Autodesk Inventor part; units mm, degrees
(part 2 of 2)
  line L877 (-195.7056, 97.218) -> (-199.6927, 97.218)
  line L878 (-201.2028, 79.0886) -> (-201.786, 79.1114)
  line L879 (-201.786, 79.1114) -> (-202.2096, 79.1804)
  line L880 (-202.2096, 79.1804) -> (-202.5152, 79.3162)
  line L881 (-202.5152, 79.3162) -> (-202.7369, 79.5481)
  line L882 (-202.7369, 79.5481) -> (-202.8877, 79.8825)
  line L883 (-202.8877, 79.8825) -> (-202.9805, 80.3189)
  line L884 (-202.9805, 80.3189) -> (-203.0286, 80.9114)
  line L885 (-203.0286, 80.9114) -> (-203.0444, 81.7214)
  line L886 (-203.0444, 81.7214) -> (-203.0056, 83.461)
  line L887 (-203.0056, 83.461) -> (-202.8887, 85.3009)
  line L888 (-202.8887, 85.3009) -> (-202.8067, 86.2924)
  line L889 (-202.8067, 86.2924) -> (-202.7609, 86.8629)
  line L890 (-202.7609, 86.8629) -> (-213.2957, 86.8629)
  line L891 (-213.2957, 86.8629) -> (-213.2957, 82.5403)
  line L892 (-213.2957, 82.5403) -> (-206.8037, 82.5403)
  line L893 (-206.8037, 82.5403) -> (-206.8797, 81.6973)
  line L894 (-206.8797, 81.6973) -> (-206.9367, 80.188)
  line L895 (-206.9367, 80.188) -> (-206.9556, 79.1924)
  line L896 (-206.9556, 79.1924) -> (-206.9328, 78.4594)
  line L897 (-206.9328, 78.4594) -> (-206.7505, 77.1615)
  line L898 (-206.7505, 77.1615) -> (-206.3859, 76.0879)
  line L899 (-206.3859, 76.0879) -> (-205.8393, 75.2383)
  line L900 (-205.8393, 75.2383) -> (-205.4975, 74.8977)
  line L901 (-205.4975, 74.8977) -> (-205.1474, 74.6369)
  line L902 (-205.1474, 74.6369) -> (-204.3364, 74.2416)
  line L903 (-204.3364, 74.2416) -> (-203.8754, 74.1066)
  line L904 (-203.8754, 74.1066) -> (-203.3727, 74.0054)
  line L905 (-203.3727, 74.0054) -> (-202.2283, 73.8896)
  line L906 (-202.2283, 73.8896) -> (-201.5863, 73.875)
  line L907 (-201.5863, 73.875) -> (-200.8617, 73.8896)
  line L908 (-200.8617, 73.8896) -> (-199.5953, 74.0054)
  line L909 (-199.5953, 74.0054) -> (-199.0535, 74.1066)
  line L910 (-199.0535, 74.1066) -> (-198.5613, 74.2416)
  line L911 (-198.5613, 74.2416) -> (-197.6925, 74.6369)
  line L912 (-197.6925, 74.6369) -> (-197.3156, 74.8977)
  line L913 (-197.3156, 74.8977) -> (-196.9763, 75.2074)
  line L914 (-196.9763, 75.2074) -> (-196.4069, 76.0064)
  line L915 (-196.4069, 76.0064) -> (-196.1771, 76.4957)
  line L916 (-196.1771, 76.4957) -> (-195.9838, 77.0457)
  line L917 (-195.9838, 77.0457) -> (-195.6961, 78.3423)
  line L918 (-195.6961, 78.3423) -> (-195.6018, 79.0886)
  line L919 (-195.6018, 79.0886) -> (-201.2028, 79.0886)
  line L920 (-213.2957, 81.4657) -> (-213.2957, 75.1774)
  line L921 (-213.2957, 75.1774) -> (-209.3327, 75.1774)
  line L922 (-209.3327, 75.1774) -> (-209.3327, 81.4657)
  line L923 (-209.3327, 81.4657) -> (-213.2957, 81.4657)
  line L924 (-195.5018, 81.3897) -> (-195.5468, 82.9417)
  line L925 (-195.5468, 82.9417) -> (-195.6816, 84.4738)
  line L926 (-195.6816, 84.4738) -> (-195.8774, 85.8811)
  line L927 (-195.8774, 85.8811) -> (-196.1132, 87.0666)
  line L928 (-196.1132, 87.0666) -> (-199.7725, 87.0666)
  line L929 (-199.7725, 87.0666) -> (-199.6257, 85.6443)
  line L930 (-199.6257, 85.6443) -> (-199.458, 83.0875)
  line L931 (-199.458, 83.0875) -> (-199.437, 81.953)
  line L932 (-199.437, 81.953) -> (-199.4501, 80.9042)
  line L933 (-199.4501, 80.9042) -> (-199.4889, 80.1632)
  line L934 (-199.4889, 80.1632) -> (-195.5259, 80.1632)
  line L935 (-195.5259, 80.1632) -> (-195.508, 80.6736)
  line L936 (-195.508, 80.6736) -> (-195.5018, 81.3897)
  line L937 (-204.5026, 62.2136) -> (-206.3415, 62.2205)
  line L938 (-206.3415, 62.2205) -> (-207.4151, 62.2415)
  line L939 (-207.4151, 62.2415) -> (-208.3299, 62.3184)
  line L940 (-208.3299, 62.3184) -> (-208.9251, 62.4453)
  line L941 (-208.9251, 62.4453) -> (-209.1228, 62.547)
  line L942 (-209.1228, 62.547) -> (-209.3963, 62.8226)
  line L943 (-209.3963, 62.8226) -> (-209.4725, 62.9965)
  line L944 (-209.4725, 62.9965) -> (-209.5595, 63.49)
  line L945 (-209.5595, 63.49) -> (-209.5884, 64.235)
  line L946 (-209.5884, 64.235) -> (-209.5753, 64.6636)
  line L947 (-209.5753, 64.6636) -> (-209.5365, 65.1818)
  line L948 (-209.5365, 65.1818) -> (-213.4755, 65.1818)
  line L949 (-213.4755, 65.1818) -> (-213.4934, 64.989)
  line L950 (-213.4934, 64.989) -> (-213.4995, 64.7224)
  line L951 (-213.4995, 64.7224) -> (-213.4995, 64.235)
  line L952 (-213.4995, 64.235) -> (-213.4714, 62.9694)
  line L953 (-213.4714, 62.9694) -> (-213.2477, 60.8979)
  line L954 (-213.2477, 60.8979) -> (-213.0521, 60.0922)
  line L955 (-213.0521, 60.0922) -> (-212.7923, 59.4113)
  line L956 (-212.7923, 59.4113) -> (-212.0572, 58.3385)
  line L957 (-212.0572, 58.3385) -> (-211.5819, 57.9468)
  line L958 (-211.5819, 57.9468) -> (-211.0734, 57.6576)
  line L959 (-211.0734, 57.6576) -> (-209.8351, 57.2621)
  line L960 (-209.8351, 57.2621) -> (-209.1049, 57.1557)
  line L961 (-209.1049, 57.1557) -> (-207.1873, 57.0389)
  line L962 (-207.1873, 57.0389) -> (-204.5026, 57)
  line L963 (-204.5026, 57) -> (-202.0716, 57.0289)
  line L964 (-202.0716, 57.0289) -> (-200.3079, 57.1158)
  line L965 (-200.3079, 57.1158) -> (-199.6211, 57.1938)
  line L966 (-199.6211, 57.1938) -> (-198.4186, 57.4814)
  line L967 (-198.4186, 57.4814) -> (-197.9029, 57.6911)
  line L968 (-197.9029, 57.6911) -> (-197.4, 57.9813)
  line L969 (-197.4, 57.9813) -> (-196.589, 58.7683)
  line L970 (-196.589, 58.7683) -> (-196.2809, 59.2651)
  line L971 (-196.2809, 59.2651) -> (-196.0303, 59.8465)
  line L972 (-196.0303, 59.8465) -> (-195.6788, 61.3205)
  line L973 (-195.6788, 61.3205) -> (-195.5778, 62.2136)
  line L974 (-195.5778, 62.2136) -> (-204.5026, 62.2136)
  line L975 (-195.5018, 64.235) -> (-195.5297, 65.4909)
  line L976 (-195.5297, 65.4909) -> (-195.7537, 67.5563)
  line L977 (-195.7537, 67.5563) -> (-195.9493, 68.3658)
  line L978 (-195.9493, 68.3658) -> (-196.2106, 69.0521)
  line L979 (-196.2106, 69.0521) -> (-196.9574, 70.1305)
  line L980 (-196.9574, 70.1305) -> (-197.4435, 70.5233)
  line L981 (-197.4435, 70.5233) -> (-197.9518, 70.8124)
  line L982 (-197.9518, 70.8124) -> (-199.1783, 71.21)
  line L983 (-199.1783, 71.21) -> (-199.8965, 71.3182)
  line L984 (-199.8965, 71.3182) -> (-201.8031, 71.432)
  line L985 (-201.8031, 71.432) -> (-204.5026, 71.4701)
  line L986 (-204.5026, 71.4701) -> (-206.9305, 71.4419)
  line L987 (-206.9305, 71.4419) -> (-208.6935, 71.3581)
  line L988 (-208.6935, 71.3581) -> (-209.3815, 71.2786)
  line L989 (-209.3815, 71.2786) -> (-210.584, 70.9889)
  line L990 (-210.584, 70.9889) -> (-211.0984, 70.7789)
  line L991 (-211.0984, 70.7789) -> (-211.6029, 70.489)
  line L992 (-211.6029, 70.489) -> (-212.4139, 69.7041)
  line L993 (-212.4139, 69.7041) -> (-212.7205, 69.2088)
  line L994 (-212.7205, 69.2088) -> (-212.971, 68.6259)
  line L995 (-212.971, 68.6259) -> (-213.3226, 67.1495)
  line L996 (-213.3226, 67.1495) -> (-213.4236, 66.2564)
  line L997 (-213.4236, 66.2564) -> (-204.5026, 66.2564)
  line L998 (-204.5026, 66.2564) -> (-202.6788, 66.2495)
  line L999 (-202.6788, 66.2495) -> (-201.6103, 66.2286)
  line L1000 (-201.6103, 66.2286) -> (-200.7154, 66.1457)
  line L1001 (-200.7154, 66.1457) -> (-200.0762, 66.0008)
  line L1002 (-200.0762, 66.0008) -> (-199.8801, 65.9)
  line L1003 (-199.8801, 65.9) -> (-199.6065, 65.6323)
  line L1004 (-199.6065, 65.6323) -> (-199.5288, 65.4654)
  line L1005 (-199.5288, 65.4654) -> (-199.4419, 64.978)
  line L1006 (-199.4419, 64.978) -> (-199.413, 64.235)
  line L1007 (-199.413, 64.235) -> (-199.413, 63.7237)
  line L1008 (-199.413, 63.7237) -> (-199.426, 63.525)
  line L1009 (-199.426, 63.525) -> (-199.4649, 63.2882)
  line L1010 (-199.4649, 63.2882) -> (-195.5259, 63.2882)
  line L1011 (-195.5259, 63.2882) -> (-195.508, 63.481)
  line L1012 (-195.508, 63.481) -> (-195.5018, 63.7477)
  line L1013 (-195.5018, 63.7477) -> (-195.5018, 64.235)
  constraints: 2028 end point, 6 parallel, 3 horizontal, 3 perpendicular
extrude "Cut1" cut sketch "Sketch3" against normal blind 2
fillet "R10 правые углы" radius 10 2 edges at (0, 120, 1) (266.0444, 120, 1)
equation "\"d0\" = Thickness"
equation "\"BendRadius\" = Thickness"
equation "\"BendReliefWidth\" = Thickness"
equation "\"BendReliefDepth\" = 0.5 * Thickness"
equation "\"CornerReliefSize\" = 4 * Thickness"
equation "\"MinimumRemnant\" = 2 * Thickness"
equation "\"TransitionRadius\" = BendRadius"
equation "\"JacobiRadiusSize\" = BendRadius"
equation "\"GapSize\" = Thickness"
equation "\"Thickness\" = 2"
body "Solid1"
